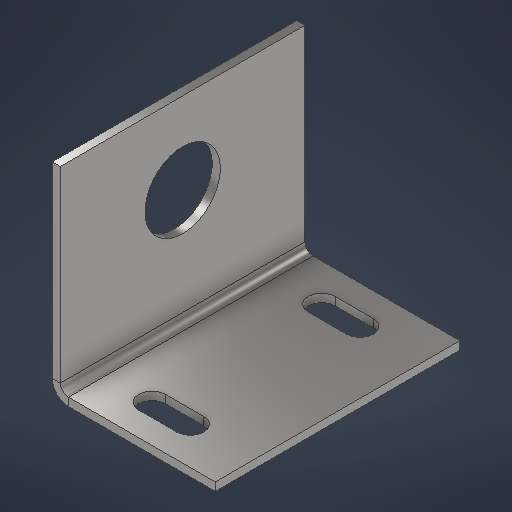
# Autodesk Inventor part: PE-BRKT-01
Saved by Autodesk Inventor 2026.2 (Build 302298000, 298)
## iProperties
Created: 2026-11-10
Part Number: PE-BRKT-01
Material: Steel, Mild
Document SubType Name: Sheet Metal
Designer: joshlev
Density: 7.85 g/cm^3
Sheet Metal Rule: Default_mm
Appearance: Semi-Polished
Description: Photo-eye bracket
Mass: 74.4406 g
Surface Area: 103.441 cm^2
Volume: 9.48287 cm^3
Flat Pattern Width: 6 cm
Flat Pattern Length: 8.65239 cm
Flat Pattern Area: 51.9143 cm^2
Sheet Metal Width: 60.000 mm
Sheet Metal Length: 86.524 mm
Sheet Metal Area: 5191.434 mm^2
Author: joshi
Autodesk Inventor part; units mm, degrees
ref_plane "YZ Plane" through (0, 0, 0) normal (1, 0, 0) x (0, 1, 0)
ref_plane "XZ Plane" through (0, 0, 0) normal (0, 1, 0) x (-1, 0, 0)
ref_plane "XY Plane" through (0, 0, 0) normal (0, 0, 1) x (1, 0, 0)
sketch "Sketch1" plane through (0, 0, 0) normal (0, 0, 1) x (1, 0, 0)
  point P0 (0, 0)
sketch "Sketch2" plane through (0, 0, 0) normal (0, 1, 0) x (-1, 0, 0)
  line L0 (20, -30) -> (-20, -30)
  line L1 (-20, -30) -> (-20, 30)
  line L2 (-20, 30) -> (20, 30)
  line L3 (20, 30) -> (20, -30)
  line L4 (20, -30) -> (-20, 30) construction
  line L5 (-20, -30) -> (20, 30) construction
  point P0 (0, 0)
  dimension "d2" = 40
  dimension "d3" = 60
  measures "d2" distance of L1.end L2.end
  measures "d3" distance of L0.end L1.end
extrude "Plate1" add sketch "Sketch2" along normal blind 2
sketch "Sketch3" plane through (-18, 0, 30) normal (-1, 0, 0) x (0, -1, 0)
  line L0 (0, -60) -> (0, 0)
  line L1 (0, 0) -> (-50, 0)
  line L2 (-50, 0) -> (-50, -60)
  line L3 (-50, -60) -> (0, -60)
  constraints: 6 end point, 1 horizontal, 1 perpendicular, 1 vertical
edge flange "Flange1" height 50 angle 90 thickness 2 bend radius 2 thickness toward (-1, 0, 0) relief tear relief width 2 relief depth 1 edges at (-20, 2, 0) wall of the first edge with corners at (-18, 0, -30) (-18, 0, 30) (-18, 50, 30) (-18, 50, -30)
bend "Bend1"
corner "Corner1"
sketch "Sketch4" plane through (0, 2, 0) normal (0, 1, 0) x (1, 0, 0)
  line L0 (-4.7, -20.8) -> (4.7, -20.8) construction
  line L1 (-4.7, -24.1) -> (4.7, -24.1)
  line L2 (4.7, -17.5) -> (-4.7, -17.5)
  arc A0 (-4.7, -17.5) -> (-4.7, -24.1) centre (-4.7, -20.8) ccw
  arc A1 (4.7, -24.1) -> (4.7, -17.5) centre (4.7, -20.8) ccw
  line L3 (0, 0) -> (20, 0) construction
  line L4 (20, 30) -> (20, -30) projected
  line L5 (-4.7, 20.8) -> (4.7, 20.8) construction
  line L6 (-4.7, 24.1) -> (4.7, 24.1)
  line L7 (4.7, 17.5) -> (-4.7, 17.5)
  arc A2 (-4.7, 24.1) -> (-4.7, 17.5) centre (-4.7, 20.8) ccw
  arc A3 (4.7, 17.5) -> (4.7, 24.1) centre (4.7, 20.8) ccw
  point P0 (0, -20.8)
  point P1 (0, 20.8)
  dimension "d15" = 9.4
  dimension "d16" = 6.6
  dimension "d17" = 17.5
  constraints: 18 end point, 8 point on circle, 7 symmetric about line, 4 centre point, 4 tangent, 2 horizontal, 2 midpoint, 1 parallel, 1 vertical alignment, 2 other
  measures "d15" distance of L0.start L0.end
  measures "d16" diameter of A1
  measures "d17" distance from line of L3.start L2
extrude "Cut1" cut sketch "Sketch4" against normal through all
sketch "Sketch5" plane through (-18, 50, 30) normal (1, 0, 0) x (0, 0, -1)
  line L0 (60, -46) -> (60, 0) projected
  line L1 (60, 0) -> (0, 0) projected
  point P0 (30, -50)
  point P1 (30, -20)
  point P2 (30, 0)
  dimension "d20" = 30
  dimension "d21" = 20
  constraints: 1 midpoint
  measures "d20" distance from line of L0 point (30, -20)
  measures "d21" distance of point (30, 0) point (30, -20)
hole "Hole1" at (-18, 30, 0) direction (-1, 0, 0) diameter 18.5 end through all
equation "\"d18\" = Thickness"
equation "\"d27\" = Thickness"
equation "\"d4\" = Thickness"
equation "\"d5\" = BendReliefWidth"
equation "\"d6\" = BendReliefDepth"
equation "\"d7\" = MinimumRemnant"
equation "\"d8\" = TransitionRadius"
equation "\"d11\" = BendRadius"
equation "\"d12\" = CornerReliefSize"
equation "\"d13\" = GapSize"
equation "\"d14\" = JacobiRadiusSize"
equation "\"BendRadius\" = Thickness"
equation "\"BendReliefWidth\" = Thickness"
equation "\"BendReliefDepth\" = 0.5 * Thickness"
equation "\"CornerReliefSize\" = 4 * Thickness"
equation "\"MinimumRemnant\" = 2 * Thickness"
equation "\"TransitionRadius\" = BendRadius"
equation "\"JacobiRadiusSize\" = BendRadius"
equation "\"GapSize\" = Thickness"
equation "\"Thickness\" = 2"
body "Solid1"
